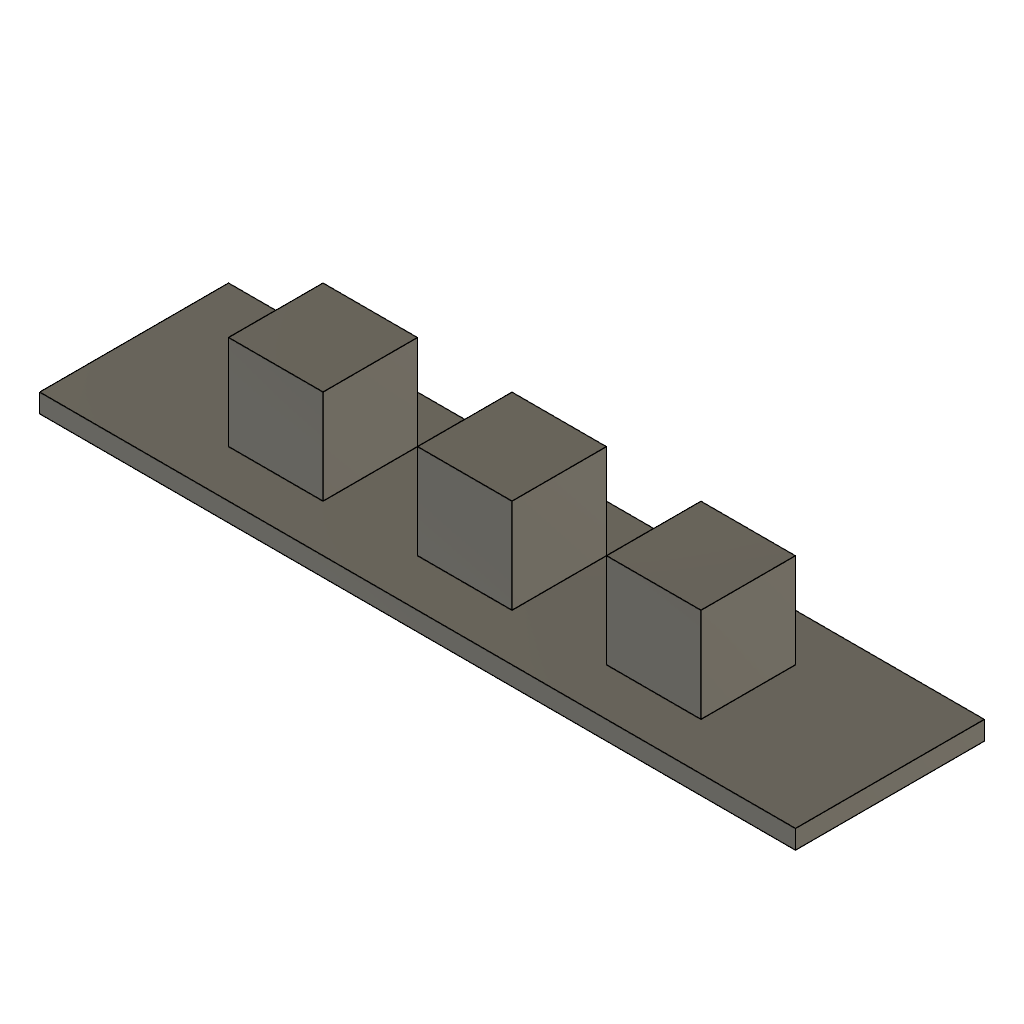
combine_pattern_copies (Autodesk Fusion 360 design; units mm, degrees)
Autodesk Fusion 360 part; units mm, degrees
sketch "Sketch1" plane through (0, 0, 0) normal (0, 0, 1) x (1, 0, 0)
  line L0 (-15, -5) -> (65, -5)
  line L1 (65, -5) -> (65, 15)
  line L2 (65, 15) -> (-15, 15)
  line L3 (-15, 15) -> (-15, -5)
extrude "Extrude1" add sketch "Sketch1" along normal blind 2 makes body 1
ref_plane "WorkPlane1" through (0, 0, 2) normal (0, 0, 1) x (1, 0, 0)
sketch "Sketch2" plane through (0, 0, 2) normal (0, 0, 1) x (1, 0, 0)
  line L0 (0, 0) -> (10, 0)
  line L1 (10, 0) -> (10, 10)
  line L2 (10, 10) -> (0, 10)
  line L3 (0, 10) -> (0, 0)
extrude "Extrude2" add sketch "Sketch2" along normal blind 10 separate body makes body 2
pattern_linear "R-Pattern1" count 3 spacing 20 along (1, 0, 0) of bodies 2 makes body 3 at (20, 6.6667, 5.3333) makes body 4 at (40, 6.6667, 5.3333)
combine "Combine1" operation add target body 1 tool bodies 3 4
named bodies: "Plate", "Seed", "Copy1", "Copy2"
